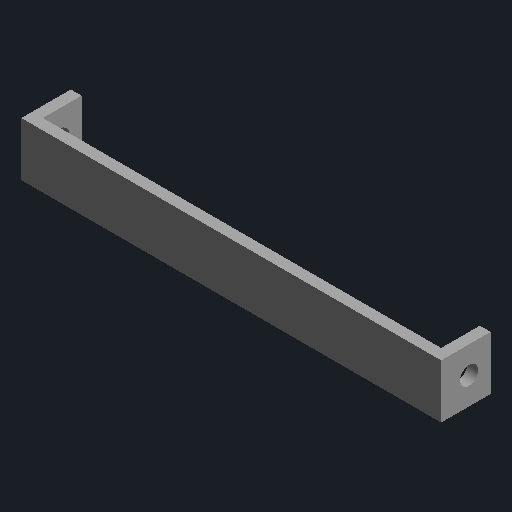
# Autodesk Inventor part: Torso_barra_bateria
Saved by Autodesk Inventor 2027 (Build 310192060, 192F)
## iProperties
Part Number: Torso_barra_bateria
Material: Genérico
Document SubType Name: Modelado
Designer: rodri
Appearance: Por defecto
Author: rodri
Autodesk Inventor part; units mm, degrees
ref_plane "Plano de trabajo1" through (0, 0, 49.2) normal (0, 0, 1) x (1, 0, 0)
sketch "Boceto1" plane through (0, 0, 49.2) normal (0, 0, 1) x (1, 0, 0)
  line L0 (-39, 16) -> (39, 16)
  line L1 (39, 16) -> (39, 26)
  line L2 (39, 26) -> (-39, 26)
  line L3 (-39, 26) -> (-39, 16)
  constraints: 8 end point, 2 parallel, 1 horizontal, 1 perpendicular
extrude "Extrusión1" add sketch "Boceto1" along normal blind 2
ref_plane "Plano de trabajo2" through (0, 0, 42) normal (0, 0, 1) x (1, 0, 0)
sketch "Boceto2" plane through (0, 0, 42) normal (0, 0, 1) x (1, 0, 0)
  line L0 (37, 16) -> (39, 16)
  line L1 (39, 16) -> (39, 26)
  line L2 (39, 26) -> (37, 26)
  line L3 (37, 26) -> (37, 16)
  constraints: 8 end point, 2 parallel, 1 horizontal, 1 perpendicular
extrude "Extrusión2" add sketch "Boceto2" along normal blind 7.2
ref_plane "Plano de trabajo3" through (36.9, 0, 0) normal (1, 0, 0) x (0, 1, 0)
sketch "Boceto3" plane through (36.9, 0, 0) normal (1, 0, 0) x (0, 1, 0)
  circle A0 centre (21, 46) radius 1.7
  constraints: 1 centre point
extrude "Extrusión3" cut sketch "Boceto3" along normal blind 2.2
ref_plane "Plano de trabajo4" through (0, 0, 42) normal (0, 0, 1) x (1, 0, 0)
sketch "Boceto4" plane through (0, 0, 42) normal (0, 0, 1) x (1, 0, 0)
  line L0 (-39, 16) -> (-37, 16)
  line L1 (-37, 16) -> (-37, 26)
  line L2 (-37, 26) -> (-39, 26)
  line L3 (-39, 26) -> (-39, 16)
  constraints: 8 end point, 2 parallel, 1 horizontal, 1 perpendicular
extrude "Extrusión4" add sketch "Boceto4" along normal blind 7.2
ref_plane "Plano de trabajo5" through (-39.1, 0, 0) normal (1, 0, 0) x (0, 1, 0)
sketch "Boceto5" plane through (-39.1, 0, 0) normal (1, 0, 0) x (0, 1, 0)
  circle A0 centre (21, 46) radius 1.7
  constraints: 1 centre point
extrude "Extrusión5" cut sketch "Boceto5" along normal blind 2.2
ref_plane "Plano de trabajo6" through (0, 0, 0) normal (0, 1, 0) x (0, 0, 1)
ref_plane "Plano de trabajo7" through (0, 0, 0) normal (1, 0, 0) x (0, 0, -1)
